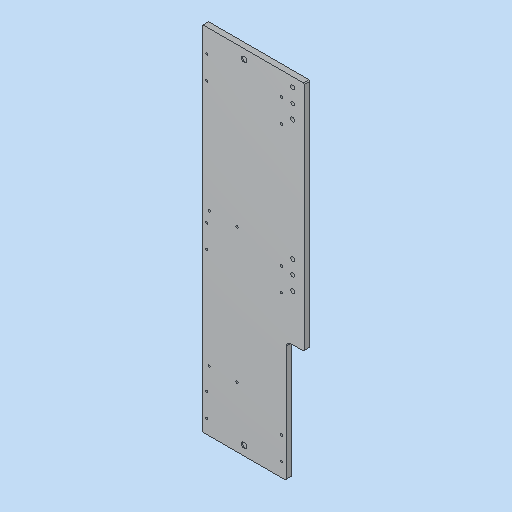
# Autodesk Inventor part: MM0948AN180_G01_104
Saved by Autodesk Inventor 2023.3 (Build 273359000, 359)
## iProperties
RuleStatus: InUse
Created: 2023-03-23
Part Number: MM0948AN180_G01_104
Material: 3.3547 AlMg4,5Mn0,7 - AW 5083
Description: =<RBPARTNOTITLE2>
Document SubType Name: Modeling
Designer: ric7an
Mass: 5066.49 g
Surface Area: 3413.08 cm^2
Volume: 1876.48 cm^3
Density: 2.7 g/cm^3
Appearance: Aluminium AnP
AnP_Kategorie: 1
AnP_Material: =<Material>
MaxAbmaße: 12 x 760 x 220 (FM)
AnP_TemplVers: 20200821
RBDOCUMENTTYPE: DRF
RBDOCUMENTVERSION: 00
RBDRAWINGMAINSCALE: 1:1
RBDRAWINGMISSINGSPEC: --
RBDRAWINGVOLUME: --
RBDSV1: 0850
RBGBEDGESIN1: +0,5
RBGBEDGESIN2: +0,2
RBGBEDGESOUT1: -0,3
RBGBEDGESOUT2: -0,1
RBMATERIAL: =<Material>
RBMATMEETS: --
RBMATNO: =<Part Number>
RBPARTMADEOF: 12 x 760 x 220 (FM)
RBPARTNO: SIEHE MNR
RBPARTNOTITLE1: manufactured part
RBPARTNOTITLE2: Anfertigungsteil
RBPARTSAFETYINDICATOR: --
RBSURFACE: anodised colourless
RBSURFACE2: eloxiert farblos
RBZEDGESNORM: ISO13715:2002-06
RBZGENDIMCLASS: m
RBZGENDIMNORM: ISO 2768-1:1989-11
RBZGENGEOCLASS: H
RBZGENGEONORM: ISO 2768-2:1989-11
RBZSURFACENORM: ISO13D2:2002-02
RBZTOLERANCENORM: ISO 14405-1:2010-12
AnP_Kommentar_aktuell: =<Comments>
AnP_Material_aktuell: =<Material>
Author: FH/Wi
Keywords: =<RBPARTMADEOF>
Comments: =<RBSURFACE2>
Revision Number: 01
Autodesk Inventor part; units mm, degrees
ref_plane "YZ Plane" through (0, 0, 0) normal (1, 0, 0) x (0, 1, 0)
ref_plane "XZ Plane" through (0, 0, 0) normal (0, 1, 0) x (-1, 0, 0)
ref_plane "XY Plane" through (0, 0, 0) normal (0, 0, 1) x (1, 0, 0)
sketch "Skizze1" plane through (0, 0, 0) normal (0, 0, 1) x (1, 0, 0)
  line L0 (-110, 760) -> (110, 760)
  line L1 (110, 760) -> (110, 0)
  line L2 (110, 0) -> (-110, 0)
  line L3 (-110, 0) -> (-110, 760)
  line L4 (0, 912) -> (0, -152) projected
  line L5 (-154, 0) -> (154, 0) projected
  point P0 (0, 0)
  dimension "d0" = 760
  dimension "d1" = 220
  constraints: 8 end point, 2 parallel, 1 collinear, 1 horizontal, 1 perpendicular, 1 other
  measures "d0" distance of L0.end L1.end
  measures "d1" distance of L0.start L0.end
extrude "Extrusion1" add sketch "Skizze1" along normal blind 12
sketch "Skizze2" plane through (0, 0, 12) normal (0, 0, 1) x (1, 0, 0)
  line L0 (-110, 760) -> (-110, 0) projected
  line L1 (110, 760) -> (-110, 760) projected
  point P0 (0, 0)
  point P1 (-100, 710)
  point P2 (-100, 660)
  point P3 (61, 710)
  point P4 (61, 660)
  point P5 (-100, 30)
  point P6 (-100, 80)
  point P7 (-100, 395)
  point P8 (-100, 345)
  point P9 (61, 395)
  point P10 (61, 345)
  point P11 (61, 80)
  point P12 (61, 30)
  dimension "d4" = 50
  dimension "d5" = 161
  dimension "d6" = 10
  dimension "d7" = 50
  dimension "d15" = 680
  dimension "d16" = 50
  dimension "d17" = 315
  dimension "d18" = 50
  constraints: 10 vertical alignment, 6 horizontal alignment
  measures "d4" distance of point (-100, 660) point (-100, 710)
  measures "d5" distance of point (61, 710) point (-100, 710)
  measures "d6" distance from line of point (-100, 710) L0
  measures "d7" distance from line of L1 point (-100, 710)
  measures "d15" distance of point (-100, 30) point (-100, 710)
  measures "d16" distance of point (-100, 30) point (-100, 80)
  measures "d17" distance of point (-100, 395) point (-100, 710)
  measures "d18" distance of point (-100, 345) point (-100, 395)
hole "Bohrung1" at (-100, 710, 12) at (-100, 660, 12) at (61, 710, 12) at (61, 660, 12) at (61, 345, 12) at (61, 395, 12) at (-100, 345, 12) at (-100, 395, 12) at (61, 30, 12) at (61, 80, 12) at (-100, 80, 12) at (-100, 30, 12) direction (0, 0, -1) diameter 4.917 end through all thread size "M6x1" designation "M6" class "6H" standard "ISO Metric profile"
sketch "Skizze3" plane through (0, 0, 12) normal (0, 0, 1) x (1, 0, 0)
  circle A0 centre (-100, 710) radius 2.4585 projected
  circle A1 centre (61, 710) radius 2.4585 projected
  line L0 (-110, 0) -> (110, 0) projected
  point P0 (0, 0)
  point P1 (-19.5, 740)
  point P2 (-19.5, 20)
  dimension "d19" = 80.5
  dimension "d20" = 20
  dimension "d21" = 720
  constraints: 1 vertical alignment
  measures "d19" horizontal distance of point (-19.5, 740) A0.centre
  measures "d20" distance from line of L0 point (-19.5, 20)
  measures "d21" distance of point (-19.5, 20) point (-19.5, 740)
hole "Bohrung2" at (-19.5, 740, 12) at (-19.5, 20, 12) direction (0, 0, -1) diameter 12 depth 2.1
sketch "Skizze4" plane through (0, 0, 0) normal (0, 0, -1) x (-1, 0, 0)
  line L0 (-110, 760) -> (110, 760) projected
  line L1 (-110, 0) -> (-110, 760) projected
  point P0 (0, 0)
  point P1 (35, 420)
  point P2 (95, 420)
  point P3 (35, 130)
  point P4 (95, 130)
  dimension "d29" = 340
  dimension "d30" = 145
  dimension "d31" = 290
  dimension "d32" = 60
  constraints: 2 horizontal alignment, 2 vertical alignment
  measures "d29" distance from line of L0 point (35, 420)
  measures "d30" distance from line of point (35, 420) L1
  measures "d31" distance of point (35, 130) point (35, 420)
  measures "d32" distance of point (95, 420) point (35, 420)
hole "Bohrung3" at (-35, 420, 0) at (-95, 420, 0) at (-35, 130, 0) at (-95, 130, 0) direction (0, 0, 1) diameter 4.917 end through all thread size "M6x1" designation "M6" class "6H" standard "ISO Metric profile"
sketch "Skizze5" plane through (0, 0, 12) normal (0, 0, 1) x (1, 0, 0)
  line L0 (110, 760) -> (-110, 760) projected
  line L1 (110, 0) -> (110, 760) projected
  point P0 (0, 0)
  point P1 (85, 740)
  point P2 (85, 680)
  point P3 (85, 420)
  point P4 (85, 360)
  dimension "d40" = 60
  dimension "d41" = 60
  dimension "d42" = 320
  dimension "d44" = 20
  dimension "d45" = 25
  constraints: 3 vertical alignment
  measures "d40" distance of point (85, 680) point (85, 740)
  measures "d41" distance of point (85, 360) point (85, 420)
  measures "d42" distance of point (85, 420) point (85, 740)
  measures "d44" distance from line of L0 point (85, 740)
  measures "d45" distance from line of L1 point (85, 740)
hole "Bohrung4" at (85, 740, 12) at (85, 680, 12) at (85, 420, 12) at (85, 360, 12) direction (0, 0, -1) diameter 9 end through all clearance for "Inbusschraube ISO 4762  versenkt" size "M8" standard "ISO"
sketch "Skizze6" plane through (0, 0, 12) normal (0, 0, 1) x (1, 0, 0)
  circle A0 centre (85, 740) radius 4.5 projected
  circle A1 centre (85, 420) radius 4.5 projected
  point P0 (0, 0)
  point P1 (85, 710)
  point P2 (85, 390)
  dimension "d53" = 30
  dimension "d54" = 30
  constraints: 2 vertical alignment
  measures "d53" distance of point (85, 710) A0.centre
  measures "d54" distance of point (85, 390) A1.centre
hole "Bohrung5" at (85, 710, 12) at (85, 390, 12) direction (0, 0, -1) diameter 8 end through all
sketch "Skizze7" plane through (0, 0, 12) normal (0, 0, 1) x (1, 0, 0)
  line L0 (110, 260) -> (71, 260)
  line L1 (71, 260) -> (71, 0)
  line L2 (71, 0) -> (110, 0)
  line L3 (110, 0) -> (110, 260)
  circle A0 centre (-100, 30) radius 2.4585 projected
  line L4 (-110, 760) -> (-110, 0) projected
  circle A1 centre (61, 30) radius 2.4585 projected
  point P0 (0, 0)
  point P1 (110, 0)
  dimension "d65" = 10
  dimension "d66" = 10
  dimension "d67" = 260
  constraints: 8 end point, 2 parallel, 1 coincident, 1 horizontal, 1 perpendicular
  measures "d65" distance from line of A0.centre L4
  measures "d66" distance from line of L1 A1.centre
  measures "d67" distance of L0.end L1.end
extrude "Extrusion2" cut sketch "Skizze7" against normal through all contours L3 L2 L1 L0
fillet "Rundung1" radius 10 1 edges at (71, 260, 6)
chamfer "Fase1" distance 2 angle 45 5 edges at (-110, 760, 6) (110, 760, 6) (-110, 0, 6) (71, 0, 6) (110, 260, 6)
equation "\"d16\" = d4"
equation "\"d18\" = d4"
equation "\"d41\" = d40"
equation "\"d66\" = d65"
